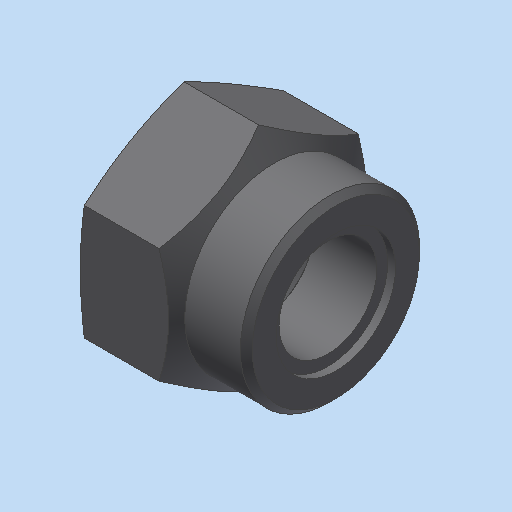
# Autodesk Inventor part: Sechskantmutter_ISO_7040___M6
Saved by Autodesk Inventor 2023.3 (Build 273359000, 359)
## iProperties
Shininess: 64.0
Length Units: 11269
Angle Units: 11279
Time Units: 11290
Mass Units: 11283
Length Display Precision: 3
Angle Display Precision: 2
Compacted: True
Part Number: Sechskantmutter_ISO_7040___M6
Document SubType Name: Modeling
Created: 2004-03-22
Material: xStahl_AnP_Dummymaterial
Description: =<RBPARTNOTITLE2>
Vendor: NORM8
Designer: S.Riedelsheimer
Manufacturer: Standard
Standards Organization: Custom
Density: 7.85 g/cm^3
Mass: 3.47058 g
Surface Area: 5.01489 cm^2
Volume: 0.442112 cm^3
Appearance: Stahl - normal AnP
Density: 0.0
Volumn: 0.0
Area: 0.0
PropertySet Name: Model Information
Control State: 0
Master: False
Checked Out: False
CNS_NB: Sechskantmutter ISO 7040 - M6
CNS_NN: ISO 7040
CNS_NT: Sechskantmutter  mit Klemmteil (mit nichtmetallischem Einsatz) Typ1
CNS_NBSYN: Sechskantmutter ISO 7040 - $NENN.
CNS_LINA: Sechskantmutter ISO 7040 - M6
CNS_NENN: M6
CNS_D: 6.000
CNS_D1: 4.920
CNS_P: 1.000
CNS_DA: 6.750
CNS_DW: 8.880
CNS_E: 11.050
CNS_M: 8.000
CNS_MG: 4.900
CNS_M1: 3.920
CNS_S: 10.000
CNS_KT: DUMMY
PSOL_IDENT_0: {C:\partsolutions8\data\23d-libs\bosch_bamberg\muttern\muttern_mit_klemmteil\din_en_iso_7040.prj},16
PSOL_IDENT_1: 5 {M=Nenngewinde},{VTYP=3D},{NB=Sechskantmutter ISO 7040 - M6},{NN=ISO 7040},{DATE=26.11.2003},{GEOM
PSOL_IDENT_2: DATE=26.11.2003},{VERSION=v2},{LINEID=40},{LINESUBID=-1},{WBVAR=}  {NB=Sechskantmutter ISO 7040 - M6
PSOL_IDENT_3: },{LINA=Sechskantmutter ISO 7040 - M6},{KT=DUMMY},{IDNR=},{NENN=M6},{D=6.000},{D1=4.920},{P=1.000},{
PSOL_IDENT_4: DA=6.750},{DW=8.880},{E=11.050},{M=8.000},{MG=4.900},{M1=3.920},{S=10.000}
RBPARTNOTITLE2: Sechskantmuttern mit Klemmteil (mit nichtmetallischem Einsatz)
RBPARTNOTITLE1: Prevailing torque type hexagon regular nuts (with non-metallic insert)
RBDRAWINGMISSINGSPEC: --
AnP_Kategorie: 4
RBPARTMADEOF: ISO 7040 - M6 - verzinkt
Title: Sechskantmutter ISO 7040 - M6
Author: S.Riedelsheimer
Keywords: =<RBPARTMADEOF>
Comments: =<RBSURFACE2>
Revision Number: 01
Autodesk Inventor part; units mm, degrees
sketch "Sketch_1" plane through (0, 0, 0) normal (0, 0, 1) x (1, 0, 0)
  line L0 (0, 0) -> (8, 0)
  line L1 (0, -4.44) -> (0.4388, -6.0775)
  line L2 (0.4388, -6.0775) -> (3.92, -6.0775)
  line L3 (3.92, -6.0775) -> (4.9, -4.5)
  line L4 (4.9, -4.5) -> (7.7, -4.5)
  line L5 (7.7, -4.5) -> (8, -4.2)
  line L6 (8, -4.2) -> (8, -3)
  line L7 (8, -3) -> (7.6, -3)
  line L8 (7.6, -3) -> (7.6, -2.46)
  line L9 (7.6, -2.46) -> (4.4, -2.46)
  line L10 (4.4, -2.46) -> (4.4, -3)
  line L11 (4.4, -3) -> (4, -3)
  line L12 (4, -3) -> (3.46, -2.46)
  line L13 (3.46, -2.46) -> (0.915, -2.46)
  line L14 (0.915, -2.46) -> (0, -3.375)
  line L15 (0, -3.375) -> (0, -4.44)
  constraints: 32 end point
revolve "Drehung1" add sketch "Sketch_1" angle 360 about axis through (0, 0, 0) along (1, 0, 0)
thread "Gewinde1" size "M6x1" class "6H" standard "ANSI Metric M Profile" length 3.625
sketch "Sketch_2" plane through (0, 0, 0) normal (-1, 0, 0) x (0, 0, 1)
  line L0 (10, 10) -> (-10, 10)
  line L1 (-10, 10) -> (-10, -10)
  line L2 (-10, -10) -> (10, -10)
  line L3 (10, -10) -> (10, 10)
  line L4 (2.8868, 5) -> (-2.8868, 5)
  line L5 (-2.8868, 5) -> (-5.7735, 0)
  line L6 (-5.7735, 0) -> (-2.8868, -5)
  line L7 (-2.8868, -5) -> (2.8868, -5)
  line L8 (2.8868, -5) -> (5.7735, 0)
  line L9 (5.7735, 0) -> (2.8868, 5)
  constraints: 20 end point
extrude "Extrusion1" cut sketch "Sketch_2" against normal blind 8.8
ref_plane "IP1_XY" through (0, 0, 0) normal (1, 0, 0) x (0, 0, -1)
ref_plane "IP1_YZ" through (0, 0, 0) normal (0, 0, -1) x (0, 1, 0)
ref_plane "IP2_XY" through (8, 0, 0) normal (1, 0, 0) x (0, 0, -1)
ref_plane "IP2_YZ" through (8, 0, 0) normal (0, 0, -1) x (0, 1, 0)
